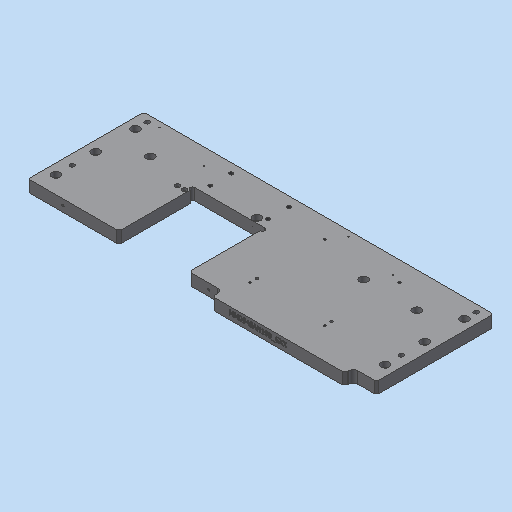
# Autodesk Inventor part: MM0948AN190_G01_101
Saved by Autodesk Inventor 2023.3 (Build 273359000, 359)
## iProperties
Created: 2023-03-23
Part Number: MM0948AN190_G01_101
Material: 1.2842 90MnCrV8
Document SubType Name: Modeling
Designer: Rose
Density: 7.85 g/cm^3
Appearance: silber AnP
Description: =<RBPARTNOTITLE2>
Mass: 32181.6 g
Surface Area: 4099.73 cm^2
Volume: 4099.57 cm^3
Project: 0850
RBMATERIAL: =<Material>
RBMATNO: =<Part Number>
RBPARTMADEOF: Präzisionsplatte 25 x 268 x 748 (FM)
RBPARTNO: SIEHE MNR
RBPARTNOTITLE1: manufactured part
RBPARTNOTITLE2: Anfertigungsteil
MaxAbmaße: 25 x 268,003 x 748 (FM)
AnP_Material_aktuell: =<Material>
AnP_Kommentar_aktuell: =<Comments>
AnP_TemplVers: 0
RBDRAWINGMISSINGSPEC: --
RBSURFACE2: chem. vernickelt
RBSURFACE: chemically nickel-coated
AnP_Kategorie: 1
AnP_Material: =<Material>
Name: MM0937AN110_G25_100.ipt
Author: FH/Wi
Keywords: =<RBPARTMADEOF>
Comments: =<RBSURFACE2>
Revision Number: 01
Autodesk Inventor part; units mm, degrees
ref_plane "YZ Plane" through (0, 0, 0) normal (1, 0, 0) x (0, 1, 0)
ref_plane "XZ Plane" through (0, 0, 0) normal (0, 1, 0) x (-1, 0, 0)
ref_plane "XY Plane" through (0, 0, 0) normal (0, 0, 1) x (1, 0, 0)
sketch "Skizze1" plane through (0, 0, 0) normal (0, 0, 1) x (1, 0, 0)
  line L0 (0, 178.6) -> (0, -196.6) projected
  line L1 (-523.6, 0) -> (523.6, 0) projected
  line L2 (-374, 125) -> (374, 125)
  line L3 (374, 125) -> (374, -143)
  line L4 (374, -143) -> (-374, -143)
  line L5 (-374, -143) -> (-374, 125)
  dimension "d1" = 748
  dimension "d259" = 125
  dimension "d260" = 143
  constraints: 8 end point, 2 parallel, 1 horizontal, 1 perpendicular, 1 other
  measures "d1" distance between parallel lines of L3 L5
  measures "d259" distance between parallel lines of L1 L2
  measures "d260" distance between parallel lines of L4 L1
extrude "Extrusion1" add sketch "Skizze1" along normal blind 25
sketch "Skizze2" plane through (0, 0, 25) normal (0, 0, 1) x (1, 0, 0)
  line L0 (0, 178.6) -> (0, -196.6) projected
  line L1 (-523.6, 0) -> (523.6, 0) projected
  line L2 (-352, 85) -> (-352, -85)
  line L3 (352, 85) -> (352, -85)
  line L4 (-374, 125) -> (-374, -143) projected
  point P0 (-352, 0)
  point P1 (352, 0)
  dimension "d4" = 22
  dimension "d5" = 170
  constraints: 4 coincident, 4 end point, 2 midpoint, 2 parallel, 1 perpendicular, 1 point on line, 1 symmetric about line
  measures "d4" distance from line of point (-352, 85) L4
  measures "d5" distance of L2.start L2.end
hole "Bohrung1" at (-352, 85, 25) at (-352, 0, 25) at (-352, -85, 25) at (352, 85, 25) at (352, 0, 25) at (352, -85, 25) direction (0, 0, -1) diameter 11 end through all counterbore diameter 18 counterbore depth 11 clearance for "Inbusschraube ISO 4762  versenkt" size "M10" standard "ISO"
sketch "Skizze3" plane through (0, 0, 25) normal (0, 0, 1) x (1, 0, 0)
  line L0 (0, 178.6) -> (0, -196.6) projected
  line L1 (-523.6, 0) -> (523.6, 0) projected
  circle A0 centre (-352, 85) radius 5.5 projected
  line L2 (-352, 85) -> (-352, 110)
  point P0 (-352, -50)
  point P1 (352, -50)
  point P2 (352, 110)
  dimension "d13" = 160
  dimension "d108" = 110
  constraints: 2 end point, 2 symmetric about line, 1 coincident, 1 perpendicular, 1 point on line
  measures "d13" distance of point (-352, -50) point (-352, 110)
  measures "d108" distance from line of L1 point (-352, 110)
hole "Bohrung2" at (-352, 110, 25) at (-352, -50, 25) at (352, -50, 25) at (352, 110, 25) direction (0, 0, -1) diameter 10 end through all
sketch "Skizze25" plane through (0, 0, 25) normal (0, 0, 1) x (1, 0, 0)
  line L0 (-324, -125) -> (-374, -125)
  line L1 (-374, -125) -> (-374, -143)
  line L2 (-374, -143) -> (-324, -143)
  line L3 (-324, -143) -> (-324, -125)
  line L4 (374, -125) -> (324, -125)
  line L5 (324, -125) -> (324, -143)
  line L6 (324, -143) -> (374, -143)
  line L7 (374, -143) -> (374, -125)
  point P0 (0, 0)
  dimension "d274" = 125
  dimension "d275" = 50
  constraints: 16 end point, 4 parallel, 2 coincident, 2 collinear, 2 horizontal, 2 perpendicular, 1 point on line
  measures "d274" distance from line of L0 point (0, 0)
  measures "d275" distance of L0.start L0.end
extrude "Extrusion3" cut sketch "Skizze25" against normal through all
fillet "Rundung1" radius 10 2 edges at (-324, -125, 12.5) (324, -125, 12.5)
chamfer "Fase1" distance 5 angle 45 6 edges at (-374, 125, 12.5) (374, 125, 12.5) (-374, -125, 12.5) (-324, -143, 12.5) (324, -143, 12.5) (374, -125, 12.5)
sketch "Skizze11" plane through (-379, -143, 0) normal (0, -1, 0) x (1, 0, 0)
  line L0 (455, 19) -> (579, 19) construction
  line L1 (579, 19) -> (579, 6) construction
  line L2 (579, 6) -> (455, 6) construction
  line L3 (455, 6) -> (455, 19) construction
  line L4 (698, 0) -> (60, 0) projected
  line L5 (5, 25) -> (5, 0) projected
  line L6 (464.5867, 8.7731) -> (463.2577, 8.7731)
  line L7 (463.2577, 8.7731) -> (463.2577, 17.3874)
  line L8 (463.2577, 17.3874) -> (460.6483, 11.5284)
  line L9 (460.6483, 11.5284) -> (459.8379, 11.5284)
  line L10 (459.8379, 11.5284) -> (457.2528, 17.3874)
  line L11 (457.2528, 17.3874) -> (457.2528, 8.7731)
  line L12 (457.2528, 8.7731) -> (456.013, 8.7731)
  line L13 (456.013, 8.7731) -> (456.013, 18.7731)
  line L14 (456.013, 18.7731) -> (457.8282, 18.7731)
  line L15 (457.8282, 18.7731) -> (460.3241, 13.2058)
  line L16 (460.3241, 13.2058) -> (462.7391, 18.7731)
  line L17 (462.7391, 18.7731) -> (464.5867, 18.7731)
  line L18 (464.5867, 18.7731) -> (464.5867, 8.7731)
  line L19 (475.1864, 8.7731) -> (473.8574, 8.7731)
  line L20 (473.8574, 8.7731) -> (473.8574, 17.3874)
  line L21 (473.8574, 17.3874) -> (471.248, 11.5284)
  line L22 (471.248, 11.5284) -> (470.4376, 11.5284)
  line L23 (470.4376, 11.5284) -> (467.8525, 17.3874)
  line L24 (467.8525, 17.3874) -> (467.8525, 8.7731)
  line L25 (467.8525, 8.7731) -> (466.6126, 8.7731)
  line L26 (466.6126, 8.7731) -> (466.6126, 18.7731)
  line L27 (466.6126, 18.7731) -> (468.4279, 18.7731)
  line L28 (468.4279, 18.7731) -> (470.9238, 13.2058)
  line L29 (470.9238, 13.2058) -> (473.3387, 18.7731)
  line L30 (473.3387, 18.7731) -> (475.1864, 18.7731)
  line L31 (475.1864, 18.7731) -> (475.1864, 8.7731)
  spline S0 degree 2 poles (483.1524, 13.7731) (483.1524, 11.0827) (481.5883, 8.5624) (479.9595, 8.5624) knots 0 0 0 1 2 2 2
  spline S1 degree 2 poles (479.9595, 8.5624) (478.3063, 8.5624) (476.7585, 11.1313) (476.7585, 13.765) knots 0 0 0 1 2 2 2
  spline S2 degree 2 poles (476.7585, 13.765) (476.7585, 16.4716) (478.3225, 18.9757) (479.9595, 18.9757) knots 0 0 0 1 2 2 2
  spline S3 degree 2 poles (479.9595, 18.9757) (481.6045, 18.9757) (483.1524, 16.3825) (483.1524, 13.7731) knots 0 0 0 1 2 2 2
  spline S4 degree 2 poles (481.4344, 10.7261) (481.6288, 11.2204) (481.7909, 12.7439) (481.7909, 13.7731) knots 0 0 0 1 2 2 2
  spline S5 degree 2 poles (481.7909, 13.7731) (481.7909, 14.8023) (481.6288, 16.3177) (481.4263, 16.8282) knots 0 0 0 1 2 2 2
  spline S6 degree 2 poles (481.4263, 16.8282) (481.2237, 17.3387) (480.5186, 17.8655) (479.9595, 17.8655) knots 0 0 0 1 2 2 2
  spline S7 degree 2 poles (479.9595, 17.8655) (479.4003, 17.8655) (478.6791, 17.3387) (478.4684, 16.812) knots 0 0 0 1 2 2 2
  spline S8 degree 2 poles (478.4684, 16.812) (478.2658, 16.3015) (478.1199, 14.7455) (478.1199, 13.765) knots 0 0 0 1 2 2 2
  spline S9 degree 2 poles (478.1199, 13.765) (478.1199, 12.7115) (478.2496, 11.3015) (478.4603, 10.7504) knots 0 0 0 1 2 2 2
  spline S10 degree 2 poles (478.4603, 10.7504) (478.6548, 10.2318) (479.376, 9.6726) (479.9595, 9.6726) knots 0 0 0 1 2 2 2
  spline S11 degree 2 poles (479.9595, 9.6726) (480.5105, 9.6726) (481.2318, 10.1994) (481.4344, 10.7261) knots 0 0 0 1 2 2 2
  spline S12 degree 2 poles (484.1572, 15.5235) (484.1572, 16.2934) (484.6596, 17.5737) (485.0972, 18.0357) knots 0 0 0 1 2 2 2
  spline S13 degree 2 poles (485.0972, 18.0357) (485.5105, 18.4814) (486.718, 18.9757) (487.3339, 18.9757) knots 0 0 0 1 2 2 2
  spline S14 degree 2 poles (487.3339, 18.9757) (488.0227, 18.9757) (489.141, 18.5138) (489.5543, 18.0762) knots 0 0 0 1 2 2 2
  spline S15 degree 2 poles (489.5543, 18.0762) (490.0729, 17.5251) (490.6402, 15.7423) (490.6402, 14.3728) knots 0 0 0 1 2 2 2
  spline S16 degree 2 poles (490.6402, 14.3728) (490.6402, 13.1329) (490.081, 10.9125) (489.5381, 10.175) knots 0 0 0 1 2 2 2
  spline S17 degree 2 poles (489.5381, 10.175) (488.9627, 9.3971) (487.342, 8.5786) (486.1588, 8.5786) knots 0 0 0 1 2 2 2
  spline S18 degree 2 poles (486.1588, 8.5786) (485.8914, 8.5786) (485.2836, 8.6353) (485.0243, 8.7164) knots 0 0 0 1 2 2 2
  line L32 (485.0243, 8.7164) -> (485.0243, 10.0049)
  line L33 (485.0243, 10.0049) -> (485.0891, 10.0049)
  spline S19 degree 2 poles (485.0891, 10.0049) (485.2593, 9.9076) (485.9724, 9.7374) (486.3371, 9.7374) knots 0 0 0 1 2 2 2
  spline S20 degree 2 poles (486.3371, 9.7374) (487.6499, 9.7374) (489.1491, 11.4716) (489.2545, 13.0762) knots 0 0 0 1 2 2 2
  spline S21 degree 2 poles (489.2545, 13.0762) (488.7196, 12.7115) (487.7472, 12.3793) (487.1718, 12.3793) knots 0 0 0 1 2 2 2
  spline S22 degree 2 poles (487.1718, 12.3793) (486.6207, 12.3793) (485.705, 12.6224) (485.2431, 12.9708) knots 0 0 0 1 2 2 2
  spline S23 degree 2 poles (485.2431, 12.9708) (484.7083, 13.3841) (484.1572, 14.6402) (484.1572, 15.5235) knots 0 0 0 1 2 2 2
  spline S24 degree 2 poles (489.2869, 14.6726) (489.2869, 15.6856) (488.9141, 16.966) (488.5818, 17.3144) knots 0 0 0 1 2 2 2
  spline S25 degree 2 poles (488.5818, 17.3144) (488.2901, 17.6386) (487.6823, 17.8817) (487.3258, 17.8817) knots 0 0 0 1 2 2 2
  spline S26 degree 2 poles (487.3258, 17.8817) (486.4992, 17.8817) (485.5186, 16.6985) (485.5186, 15.5802) knots 0 0 0 1 2 2 2
  spline S27 degree 2 poles (485.5186, 15.5802) (485.5186, 14.9481) (485.8428, 14.1297) (486.1994, 13.8379) knots 0 0 0 1 2 2 2
  spline S28 degree 2 poles (486.1994, 13.8379) (486.4587, 13.6272) (487.0989, 13.4895) (487.4716, 13.4895) knots 0 0 0 1 2 2 2
  spline S29 degree 2 poles (487.4716, 13.4895) (487.9011, 13.4895) (488.8898, 13.7893) (489.2626, 14.0405) knots 0 0 0 1 2 2 2
  spline S30 degree 2 poles (489.2626, 14.0405) (489.2707, 14.1378) (489.2869, 14.47) (489.2869, 14.6726) knots 0 0 0 1 2 2 2
  line L34 (498.3712, 12.2091) -> (497.1799, 12.2091)
  line L35 (497.1799, 12.2091) -> (497.1799, 8.7731)
  line L36 (497.1799, 8.7731) -> (495.8914, 8.7731)
  line L37 (495.8914, 8.7731) -> (495.8914, 12.2091)
  line L38 (495.8914, 12.2091) -> (491.4749, 12.2091)
  line L39 (491.4749, 12.2091) -> (491.4749, 13.6191)
  line L40 (491.4749, 13.6191) -> (495.9481, 18.7731)
  line L41 (495.9481, 18.7731) -> (497.1799, 18.7731)
  line L42 (497.1799, 18.7731) -> (497.1799, 13.2869)
  line L43 (497.1799, 13.2869) -> (498.3712, 13.2869)
  line L44 (498.3712, 13.2869) -> (498.3712, 12.2091)
  line L45 (495.8914, 13.2869) -> (495.8914, 17.1929)
  line L46 (495.8914, 17.1929) -> (492.5284, 13.2869)
  line L47 (492.5284, 13.2869) -> (495.8914, 13.2869)
  spline S31 degree 2 poles (502.4635, 8.5462) (501.718, 8.5462) (500.4943, 8.9919) (500.0648, 9.4052) knots 0 0 0 1 2 2 2
  spline S32 degree 2 poles (500.0648, 9.4052) (499.6434, 9.8104) (499.2058, 10.9125) (499.2058, 11.5365) knots 0 0 0 1 2 2 2
  spline S33 degree 2 poles (499.2058, 11.5365) (499.2058, 12.3468) (500.0729, 13.7083) (500.8995, 14.1135) knots 0 0 0 1 2 2 2
  line L48 (500.8995, 14.1135) -> (500.8995, 14.154)
  spline S34 degree 2 poles (500.8995, 14.154) (500.1621, 14.5835) (499.4489, 15.6045) (499.4489, 16.3663) knots 0 0 0 1 2 2 2
  spline S35 degree 2 poles (499.4489, 16.3663) (499.4489, 17.4927) (501.1507, 19) (502.4635, 19) knots 0 0 0 1 2 2 2
  spline S36 degree 2 poles (502.4635, 19) (503.825, 19) (505.47, 17.5737) (505.47, 16.4554) knots 0 0 0 1 2 2 2
  spline S37 degree 2 poles (505.47, 16.4554) (505.47, 15.7828) (504.684, 14.47) (503.9465, 14.0972) knots 0 0 0 1 2 2 2
  line L49 (503.9465, 14.0972) -> (503.9465, 14.0567)
  spline S38 degree 2 poles (503.9465, 14.0567) (504.8217, 13.6515) (505.7212, 12.4846) (505.7212, 11.5608) knots 0 0 0 1 2 2 2
  spline S39 degree 2 poles (505.7212, 11.5608) (505.7212, 10.2804) (503.8574, 8.5462) (502.4635, 8.5462) knots 0 0 0 1 2 2 2
  spline S40 degree 2 poles (504.3436, 11.4311) (504.3436, 12.047) (503.8574, 12.7763) (503.1686, 13.1491) knots 0 0 0 1 2 2 2
  spline S41 degree 2 poles (503.1686, 13.1491) (502.9417, 13.2788) (502.1799, 13.5786) (501.7018, 13.7731) knots 0 0 0 1 2 2 2
  spline S42 degree 2 poles (501.7018, 13.7731) (501.1507, 13.4084) (500.5592, 12.3225) (500.5592, 11.6337) knots 0 0 0 1 2 2 2
  spline S43 degree 2 poles (500.5592, 11.6337) (500.5592, 10.7261) (501.6532, 9.5429) (502.4797, 9.5429) knots 0 0 0 1 2 2 2
  spline S44 degree 2 poles (502.4797, 9.5429) (503.3225, 9.5429) (504.3436, 10.5559) (504.3436, 11.4311) knots 0 0 0 1 2 2 2
  spline S45 degree 2 poles (504.1572, 16.4392) (504.1572, 17.1118) (503.2577, 18.0113) (502.4554, 18.0113) knots 0 0 0 1 2 2 2
  spline S46 degree 2 poles (502.4554, 18.0113) (501.7261, 18.0113) (500.7942, 17.2091) (500.7942, 16.5203) knots 0 0 0 1 2 2 2
  spline S47 degree 2 poles (500.7942, 16.5203) (500.7942, 16.0259) (501.2723, 15.3371) (501.7504, 15.0616) knots 0 0 0 1 2 2 2
  spline S48 degree 2 poles (501.7504, 15.0616) (501.953, 14.9481) (502.812, 14.5511) (503.1605, 14.4376) knots 0 0 0 1 2 2 2
  spline S49 degree 2 poles (503.1605, 14.4376) (503.7439, 14.8833) (504.1572, 15.8314) (504.1572, 16.4392) knots 0 0 0 1 2 2 2
  line L50 (506.1507, 8.7731) -> (509.5219, 18.7731)
  line L51 (509.5219, 18.7731) -> (511.1588, 18.7731)
  line L52 (511.1588, 18.7731) -> (514.53, 8.7731)
  line L53 (514.53, 8.7731) -> (513.128, 8.7731)
  line L54 (513.128, 8.7731) -> (512.2204, 11.5689)
  line L55 (512.2204, 11.5689) -> (508.4036, 11.5689)
  line L56 (508.4036, 11.5689) -> (507.4959, 8.7731)
  line L57 (507.4959, 8.7731) -> (506.1507, 8.7731)
  line L58 (511.8558, 12.7034) -> (510.3079, 17.4117)
  line L59 (510.3079, 17.4117) -> (508.7682, 12.7034)
  line L60 (508.7682, 12.7034) -> (511.8558, 12.7034)
  line L61 (522.6337, 8.7731) -> (521.1426, 8.7731)
  line L62 (521.1426, 8.7731) -> (516.718, 17.3955)
  line L63 (516.718, 17.3955) -> (516.718, 8.7731)
  line L64 (516.718, 8.7731) -> (515.4781, 8.7731)
  line L65 (515.4781, 8.7731) -> (515.4781, 18.7731)
  line L66 (515.4781, 18.7731) -> (517.3663, 18.7731)
  line L67 (517.3663, 18.7731) -> (521.3938, 10.8558)
  line L68 (521.3938, 10.8558) -> (521.3938, 18.7731)
  line L69 (521.3938, 18.7731) -> (522.6337, 18.7731)
  line L70 (522.6337, 18.7731) -> (522.6337, 8.7731)
  line L71 (530.0405, 8.7731) -> (525.1621, 8.7731)
  line L72 (525.1621, 8.7731) -> (525.1621, 9.7942)
  line L73 (525.1621, 9.7942) -> (526.9773, 9.7942)
  line L74 (526.9773, 9.7942) -> (526.9773, 16.4959)
  line L75 (526.9773, 16.4959) -> (525.1621, 16.4959)
  line L76 (525.1621, 16.4959) -> (525.1621, 17.4117)
  spline S50 degree 2 poles (525.1621, 17.4117) (526.1912, 17.4117) (527.1637, 17.9951) (527.2285, 18.8055) knots 0 0 0 1 2 2 2
  line L77 (527.2285, 18.8055) -> (528.2658, 18.8055)
  line L78 (528.2658, 18.8055) -> (528.2658, 9.7942)
  line L79 (528.2658, 9.7942) -> (530.0405, 9.7942)
  line L80 (530.0405, 9.7942) -> (530.0405, 8.7731)
  spline S51 degree 2 poles (531.6045, 15.5235) (531.6045, 16.2934) (532.107, 17.5737) (532.5446, 18.0357) knots 0 0 0 1 2 2 2
  spline S52 degree 2 poles (532.5446, 18.0357) (532.9579, 18.4814) (534.1653, 18.9757) (534.7812, 18.9757) knots 0 0 0 1 2 2 2
  spline S53 degree 2 poles (534.7812, 18.9757) (535.47, 18.9757) (536.5883, 18.5138) (537.0016, 18.0762) knots 0 0 0 1 2 2 2
  spline S54 degree 2 poles (537.0016, 18.0762) (537.5203, 17.5251) (538.0875, 15.7423) (538.0875, 14.3728) knots 0 0 0 1 2 2 2
  spline S55 degree 2 poles (538.0875, 14.3728) (538.0875, 13.1329) (537.5284, 10.9125) (536.9854, 10.175) knots 0 0 0 1 2 2 2
  spline S56 degree 2 poles (536.9854, 10.175) (536.41, 9.3971) (534.7893, 8.5786) (533.6062, 8.5786) knots 0 0 0 1 2 2 2
  spline S57 degree 2 poles (533.6062, 8.5786) (533.3387, 8.5786) (532.731, 8.6353) (532.4716, 8.7164) knots 0 0 0 1 2 2 2
  line L81 (532.4716, 8.7164) -> (532.4716, 10.0049)
  line L82 (532.4716, 10.0049) -> (532.5365, 10.0049)
  spline S58 degree 2 poles (532.5365, 10.0049) (532.7066, 9.9076) (533.4198, 9.7374) (533.7844, 9.7374) knots 0 0 0 1 2 2 2
  spline S59 degree 2 poles (533.7844, 9.7374) (535.0972, 9.7374) (536.5964, 11.4716) (536.7018, 13.0762) knots 0 0 0 1 2 2 2
  spline S60 degree 2 poles (536.7018, 13.0762) (536.1669, 12.7115) (535.1945, 12.3793) (534.6191, 12.3793) knots 0 0 0 1 2 2 2
  spline S61 degree 2 poles (534.6191, 12.3793) (534.0681, 12.3793) (533.1524, 12.6224) (532.6904, 12.9708) knots 0 0 0 1 2 2 2
  spline S62 degree 2 poles (532.6904, 12.9708) (532.1556, 13.3841) (531.6045, 14.6402) (531.6045, 15.5235) knots 0 0 0 1 2 2 2
  spline S63 degree 2 poles (536.7342, 14.6726) (536.7342, 15.6856) (536.3614, 16.966) (536.0292, 17.3144) knots 0 0 0 1 2 2 2
  spline S64 degree 2 poles (536.0292, 17.3144) (535.7374, 17.6386) (535.1297, 17.8817) (534.7731, 17.8817) knots 0 0 0 1 2 2 2
  spline S65 degree 2 poles (534.7731, 17.8817) (533.9465, 17.8817) (532.966, 16.6985) (532.966, 15.5802) knots 0 0 0 1 2 2 2
  spline S66 degree 2 poles (532.966, 15.5802) (532.966, 14.9481) (533.2901, 14.1297) (533.6467, 13.8379) knots 0 0 0 1 2 2 2
  spline S67 degree 2 poles (533.6467, 13.8379) (533.906, 13.6272) (534.5462, 13.4895) (534.919, 13.4895) knots 0 0 0 1 2 2 2
  spline S68 degree 2 poles (534.919, 13.4895) (535.3485, 13.4895) (536.3371, 13.7893) (536.7099, 14.0405) knots 0 0 0 1 2 2 2
  spline S69 degree 2 poles (536.7099, 14.0405) (536.718, 14.1378) (536.7342, 14.47) (536.7342, 14.6726) knots 0 0 0 1 2 2 2
  spline S70 degree 2 poles (545.6078, 13.7731) (545.6078, 11.0827) (544.0438, 8.5624) (542.4149, 8.5624) knots 0 0 0 1 2 2 2
  spline S71 degree 2 poles (542.4149, 8.5624) (540.7618, 8.5624) (539.2139, 11.1313) (539.2139, 13.765) knots 0 0 0 1 2 2 2
  spline S72 degree 2 poles (539.2139, 13.765) (539.2139, 16.4716) (540.778, 18.9757) (542.4149, 18.9757) knots 0 0 0 1 2 2 2
  spline S73 degree 2 poles (542.4149, 18.9757) (544.06, 18.9757) (545.6078, 16.3825) (545.6078, 13.7731) knots 0 0 0 1 2 2 2
  spline S74 degree 2 poles (543.8898, 10.7261) (544.0843, 11.2204) (544.2464, 12.7439) (544.2464, 13.7731) knots 0 0 0 1 2 2 2
  spline S75 degree 2 poles (544.2464, 13.7731) (544.2464, 14.8023) (544.0843, 16.3177) (543.8817, 16.8282) knots 0 0 0 1 2 2 2
  spline S76 degree 2 poles (543.8817, 16.8282) (543.6791, 17.3387) (542.9741, 17.8655) (542.4149, 17.8655) knots 0 0 0 1 2 2 2
  spline S77 degree 2 poles (542.4149, 17.8655) (541.8558, 17.8655) (541.1345, 17.3387) (540.9238, 16.812) knots 0 0 0 1 2 2 2
  spline S78 degree 2 poles (540.9238, 16.812) (540.7212, 16.3015) (540.5754, 14.7455) (540.5754, 13.765) knots 0 0 0 1 2 2 2
  spline S79 degree 2 poles (540.5754, 13.765) (540.5754, 12.7115) (540.705, 11.3015) (540.9157, 10.7504) knots 0 0 0 1 2 2 2
  spline S80 degree 2 poles (540.9157, 10.7504) (541.1102, 10.2318) (541.8314, 9.6726) (542.4149, 9.6726) knots 0 0 0 1 2 2 2
  spline S81 degree 2 poles (542.4149, 9.6726) (542.966, 9.6726) (543.6872, 10.1994) (543.8898, 10.7261) knots 0 0 0 1 2 2 2
  line L83 (553.7682, 6.7634) -> (546.0535, 6.7634)
  line L84 (546.0535, 6.7634) -> (546.0535, 7.6305)
  line L85 (546.0535, 7.6305) -> (553.7682, 7.6305)
  line L86 (553.7682, 7.6305) -> (553.7682, 6.7634)
  spline S82 degree 2 poles (558.8655, 8.5786) (557.8039, 8.5786) (556.0454, 9.2269) (555.4133, 9.8833) knots 0 0 0 1 2 2 2
  spline S83 degree 2 poles (555.4133, 9.8833) (554.7812, 10.5478) (554.1086, 12.5089) (554.1086, 13.7812) knots 0 0 0 1 2 2 2
  spline S84 degree 2 poles (554.1086, 13.7812) (554.1086, 14.9887) (554.7893, 16.9011) (555.4214, 17.5818) knots 0 0 0 1 2 2 2
  spline S85 degree 2 poles (555.4214, 17.5818) (556.0292, 18.2382) (557.812, 18.9514) (558.8736, 18.9514) knots 0 0 0 1 2 2 2
  spline S86 degree 2 poles (558.8736, 18.9514) (559.3841, 18.9514) (560.3079, 18.8055) (560.7293, 18.6759) knots 0 0 0 1 2 2 2
  spline S87 degree 2 poles (560.7293, 18.6759) (561.0697, 18.5786) (561.8963, 18.222) (562.1475, 18.0924) knots 0 0 0 1 2 2 2
  line L87 (562.1475, 18.0924) -> (562.1475, 16.4878)
  line L88 (562.1475, 16.4878) -> (562.034, 16.4878)
  spline S88 degree 2 poles (562.034, 16.4878) (561.7828, 16.7066) (561.2561, 17.1037) (560.7699, 17.3306) knots 0 0 0 1 2 2 2
  spline S89 degree 2 poles (560.7699, 17.3306) (560.3647, 17.5332) (559.3193, 17.8006) (558.7196, 17.8006) knots 0 0 0 1 2 2 2
  spline S90 degree 2 poles (558.7196, 17.8006) (557.2771, 17.8006) (555.4943, 15.6288) (555.4943, 13.8217) knots 0 0 0 1 2 2 2
  spline S91 degree 2 poles (555.4943, 13.8217) (555.4943, 12.8169) (555.9643, 11.3096) (556.41, 10.7909) knots 0 0 0 1 2 2 2
  spline S92 degree 2 poles (556.41, 10.7909) (556.8395, 10.2723) (558.0551, 9.7293) (558.8169, 9.7293) knots 0 0 0 1 2 2 2
  spline S93 degree 2 poles (558.8169, 9.7293) (559.376, 9.7293) (560.4943, 9.8914) (560.8752, 10.0535) knots 0 0 0 1 2 2 2
  line L89 (560.8752, 10.0535) -> (560.8752, 12.6386)
  line L90 (560.8752, 12.6386) -> (558.5575, 12.6386)
  line L91 (558.5575, 12.6386) -> (558.5575, 13.8055)
  line L92 (558.5575, 13.8055) -> (562.188, 13.8055)
  line L93 (562.188, 13.8055) -> (562.188, 9.4376)
  spline S94 degree 2 poles (562.188, 9.4376) (561.9368, 9.3241) (561.0778, 8.9757) (560.7131, 8.8703) knots 0 0 0 1 2 2 2
  spline S95 degree 2 poles (560.7131, 8.8703) (560.2188, 8.7245) (559.4246, 8.5786) (558.8655, 8.5786) knots 0 0 0 1 2 2 2
  line L94 (570.7699, 8.7731) -> (569.2464, 8.7731)
  line L95 (569.2464, 8.7731) -> (566.8152, 12.7601)
  line L96 (566.8152, 12.7601) -> (564.3355, 8.7731)
  line L97 (564.3355, 8.7731) -> (562.9011, 8.7731)
  line L98 (562.9011, 8.7731) -> (566.0859, 13.7812)
  line L99 (566.0859, 13.7812) -> (562.9984, 18.7731)
  line L100 (562.9984, 18.7731) -> (564.5219, 18.7731)
  line L101 (564.5219, 18.7731) -> (566.9044, 14.859)
  line L102 (566.9044, 14.859) -> (569.3355, 18.7731)
  line L103 (569.3355, 18.7731) -> (570.7699, 18.7731)
  line L104 (570.7699, 18.7731) -> (567.6418, 13.846)
  line L105 (567.6418, 13.846) -> (570.7699, 8.7731)
  line L106 (578.752, 8.7731) -> (577.2285, 8.7731)
  line L107 (577.2285, 8.7731) -> (574.7974, 12.7601)
  line L108 (574.7974, 12.7601) -> (572.3177, 8.7731)
  line L109 (572.3177, 8.7731) -> (570.8833, 8.7731)
  line L110 (570.8833, 8.7731) -> (574.0681, 13.7812)
  line L111 (574.0681, 13.7812) -> (570.9806, 18.7731)
  line L112 (570.9806, 18.7731) -> (572.5041, 18.7731)
  line L113 (572.5041, 18.7731) -> (574.8865, 14.859)
  line L114 (574.8865, 14.859) -> (577.3177, 18.7731)
  line L115 (577.3177, 18.7731) -> (578.752, 18.7731)
  line L116 (578.752, 18.7731) -> (575.624, 13.846)
  line L117 (575.624, 13.846) -> (578.752, 8.7731)
  point P0 (738, 0)
  point P1 (683, 0)
  dimension "d127" = 124
  dimension "d129" = 13
  dimension "d130" = 6
  dimension "d279" = 450
  constraints: 2 other
  measures "d127" distance of L1.end L2.end
  measures "d129" distance of L2.end L0.start
  measures "d130" distance between parallel lines of L4 L2
  measures "d279" distance between parallel lines of L3 L5
emboss "Prägen1" sketch "Skizze11" operation cut depth 0.5 direction (0, 1, 0)
sketch "Skizze13" plane through (0, 0, 25) normal (0, 0, 1) x (1, 0, 0)
  line L0 (369, 125) -> (374, 120) projected
  line L1 (369, 125) -> (-369, 125) projected
  line L2 (-374, 120) -> (-369, 125) projected
  line L3 (-374, 120) -> (-374, -120) projected
  line L4 (-319, -143) -> (319, -143) projected
  line L5 (374, -120) -> (374, 120) projected
  circle A0 centre (352, -50) radius 5 projected
  circle A1 centre (-352, 110) radius 5 projected
  circle A2 centre (-352, -50) radius 5 projected
  circle A3 centre (352, 110) radius 5 projected
  circle A4 centre (352, 0) radius 9 projected
  circle A5 centre (-352, -85) radius 9 projected
  circle A6 centre (-352, 85) radius 9 projected
  circle A7 centre (-352, 0) radius 9 projected
  circle A8 centre (352, 85) radius 9 projected
  circle A9 centre (352, -85) radius 9 projected
  line L6 (-180, -143) -> (-30, -143)
  line L7 (-30, -143) -> (-30, 40)
  line L8 (-30, 40) -> (-180, 40)
  line L9 (-180, 40) -> (-180, -143)
  line L10 (-369, -125) -> (-334, -125) projected
  arc A10 (-324, -135) -> (-334, -125) centre (-334, -135) ccw projected
  line L11 (-324, -135) -> (-324, -138) projected
  line L12 (324, -138) -> (324, -135) projected
  arc A11 (334, -125) -> (324, -135) centre (334, -135) ccw projected
  line L13 (334, -125) -> (369, -125) projected
  line L14 (374, -120) -> (369, -125) projected
  line L15 (-369, -125) -> (-374, -120) projected
  line L16 (-319, -143) -> (-324, -138) projected
  line L17 (324, -138) -> (319, -143) projected
  point P0 (0, 0)
  dimension "d131" = 150
  dimension "d132" = 180
  dimension "d133" = 85
  constraints: 8 end point, 2 parallel, 1 horizontal, 1 perpendicular, 1 point on line
  measures "d131" distance of L7.end L8.end
  measures "d132" distance from line of L9 point (0, 0)
  measures "d133" distance between parallel lines of L1 L8
extrude "Extrusion2" cut sketch "Skizze13" against normal through all contours L4 L9 L8 L7
sketch "Skizze14" plane through (0, 0, 25) normal (0, 0, 1) x (1, 0, 0)
  line L0 (369, 125) -> (-369, 125) projected
  line L1 (-167, 105) -> (-43, 105)
  line L2 (-180, 40) -> (-30, 40) projected
  point P0 (0, 0)
  point P1 (-167, 60)
  point P2 (-43, 60)
  point P3 (-105, 40)
  point P4 (-105, 105)
  dimension "d136" = 20
  dimension "d137" = 45
  dimension "d232" = 124
  constraints: 3 vertical alignment, 2 end point, 2 horizontal alignment, 2 midpoint, 1 horizontal
  measures "d136" distance from line of L1.start L0
  measures "d137" distance of point (-167, 60) L1.start
  measures "d232" distance of L1.end L1.start
hole "Bohrung11" at (-167, 105, 25) at (-43, 105, 25) at (-167, 60, 25) at (-43, 60, 25) direction (0, 0, -1) diameter 8.376 end through all thread size "M10x1.5" designation "M10" class "6H" standard "ISO Metric profile"
sketch "Skizze15" plane through (0, 0, 25) normal (0, 0, 1) x (1, 0, 0)
  line L0 (-374, 120) -> (-374, -125) projected
  line L1 (-30, -143) -> (-180, -143) projected
  point P0 (0, 0)
  point P1 (-285, 50)
  point P2 (-57, 50)
  point P3 (171, 50)
  point P4 (-374, -138)
  point P5 (285, 50)
  point P6 (-369, -143)
  dimension "d147" = 89
  dimension "d148" = 228
  dimension "d152" = 114
  dimension "d255" = 570
  dimension "d261" = 50
  constraints: 3 horizontal alignment
  measures "d147" distance from line of point (-285, 50) L0
  measures "d148" distance of point (-57, 50) point (-285, 50)
  measures "d152" distance of point (285, 50) point (171, 50)
  measures "d255" distance of point (285, 50) point (-285, 50)
  measures "d261" vertical distance of point (0, 0) point (-285, 50)
hole "Bohrung12" at (-285, 50, 25) at (-57, 50, 25) at (171, 50, 25) at (285, 50, 25) direction (0, 0, -1) diameter 11 end through all counterbore diameter 18 counterbore depth 11 clearance for "Inbusschraube ISO 4762  versenkt" size "M10" standard "ISO"
sketch "Skizze16" plane through (0, 0, 25) normal (0, 0, 1) x (1, 0, 0)
  circle A0 centre (171, 50) radius 9 projected
  circle A1 centre (-285, 50) radius 9 projected
  circle A2 centre (-57, 50) radius 9 projected
  circle A3 centre (285, 50) radius 9 projected
  circle A4 centre (-167, 60) radius 4.188 projected
  circle A5 centre (-167, 105) radius 4.188 projected
  circle A6 centre (-43, 105) radius 4.188 projected
  circle A7 centre (-43, 60) radius 4.188 projected
  circle A8 centre (352, -85) radius 9 projected
  circle A9 centre (352, 85) radius 9 projected
  circle A10 centre (-352, 0) radius 9 projected
  circle A11 centre (-352, 85) radius 9 projected
  circle A12 centre (-352, -85) radius 9 projected
  circle A13 centre (352, 0) radius 9 projected
  circle A14 centre (352, 110) radius 5 projected
  circle A15 centre (-352, -50) radius 5 projected
  circle A16 centre (-352, 110) radius 5 projected
  circle A17 centre (352, -50) radius 5 projected
  line L0 (-180, -143) -> (-180, 40) projected
  line L1 (-180, 40) -> (-30, 40) projected
  line L2 (-30, 40) -> (-30, -143) projected
  line L3 (-319, -143) -> (-180, -143) projected
  line L4 (374, -120) -> (374, 120) projected
  line L5 (369, 125) -> (374, 120) projected
  line L6 (369, 125) -> (-369, 125) projected
  line L7 (-374, 120) -> (-369, 125) projected
  line L8 (-374, 120) -> (-374, -120) projected
  line L9 (-30, -143) -> (319, -143) projected
  line L10 (324, -138) -> (324, -135) projected
  arc A18 (334, -125) -> (324, -135) centre (334, -135) ccw projected
  line L11 (334, -125) -> (369, -125) projected
  line L12 (-369, -125) -> (-334, -125) projected
  arc A19 (-324, -135) -> (-334, -125) centre (-334, -135) ccw projected
  line L13 (-324, -135) -> (-324, -138) projected
  line L14 (324, -138) -> (319, -143) projected
  line L15 (374, -120) -> (369, -125) projected
  line L16 (-369, -125) -> (-374, -120) projected
  line L17 (-319, -143) -> (-324, -138) projected
  point P0 (0, 0)
  point P1 (-180, 35)
  point P2 (-30, 35)
  dimension "d162" = 5
  dimension "d163" = 5
  constraints: 2 point on line
  measures "d162" distance from line of L1 point (-180, 35)
  measures "d163" distance from line of L1 point (-30, 35)
hole "Bohrung13" at (-180, 35, 25) at (-30, 35, 25) direction (0, 0, -1) diameter 10 end through all
sketch "Skizze18" plane through (-369, 125, 0) normal (0, 1, 0) x (1, 0, 0)
  line L0 (369, 5) -> (369, -30) projected
  line L1 (892.6, 0) -> (-154.6, 0) projected
  line L2 (189, -25) -> (339, -25) projected
  line L3 (264, -25) -> (264, 0)
  point P0 (369, 0)
  point P1 (248.1, -12.5)
  point P2 (208.1, -12.5)
  dimension "d186" = 12.5
  dimension "d188" = 40
  dimension "d233" = 15.9
  constraints: 2 end point, 1 horizontal alignment, 1 midpoint, 1 perpendicular, 1 point on line
  measures "d186" distance from line of L1 point (248.1, -12.5)
  measures "d188" distance of point (248.1, -12.5) point (208.1, -12.5)
  measures "d233" distance from line of L3 point (248.1, -12.5)
hole "Bohrung15" at (-120.9, 125, 12.5) at (-160.9, 125, 12.5) direction (0, -1, 0) diameter 4.917 depth 12 tip angle 118 thread size "M6x1" designation "M6" class "6H" standard "ISO Metric profile"
sketch "Skizze19" plane through (-369, 125, 0) normal (0, 1, 0) x (1, 0, 0)
  line L0 (369, 5) -> (369, -30) projected
  line L1 (892.6, 0) -> (-154.6, 0) projected
  circle A0 centre (248.1, -12.5) radius 2.4585 projected
  circle A1 centre (208.1, -12.5) radius 2.4585 projected
  point P0 (369, 0)
  point P1 (48.1, -12.5)
  point P2 (148.1, -12.5)
  point P3 (308.1, -12.5)
  point P4 (508.1, -12.5)
  dimension "d196" = 12.5
  dimension "d198" = 100
  dimension "d200" = 200
  dimension "d256" = 160
  dimension "d257" = 40
  dimension "d258" = 60
  constraints: 3 horizontal alignment
  measures "d196" distance from line of L1 point (148.1, -12.5)
  measures "d198" distance of point (48.1, -12.5) point (148.1, -12.5)
  measures "d200" distance of point (508.1, -12.5) point (308.1, -12.5)
  measures "d256" distance of point (308.1, -12.5) point (148.1, -12.5)
  measures "d257" distance of A0.centre A1.centre
  measures "d258" distance of point (308.1, -12.5) A0.centre
hole "Bohrung16" at (-320.9, 125, 12.5) at (-220.9, 125, 12.5) at (-60.9, 125, 12.5) at (139.1, 125, 12.5) direction (0, -1, 0) diameter 3.242 depth 11.8 tip angle 118 thread size "M4x0.7" designation "M4" class "6H" standard "ISO Metric profile"
chamfer "Fase3" distance 10 angle 45 2 edges at (-180, -143, 12.5) (-30, -143, 12.5)
sketch "Skizze22" plane through (-123.43, 16.1933, 25) normal (0, 0, 1) x (1, 0, 0)
  line L0 (103.43, -159.1933) -> (447.43, -159.1933) projected
  point P0 (178.43, -93.1933)
  point P1 (178.43, 66.8067)
  point P2 (338.43, 66.8067)
  point P3 (338.43, -93.1933)
  point P4 (492.43, -159.1933)
  point P5 (123.43, -16.1933)
  dimension "d236" = 160
  dimension "d235" = 160
  dimension "d254" = 55
  dimension "d263" = 77
  constraints: 2 horizontal alignment, 2 vertical alignment
  measures "d236" distance of point (338.43, -93.193) point (178.43, -93.193)
  measures "d235" distance of point (338.43, -93.193) point (338.43, 66.807)
  measures "d254" horizontal distance of point (178.43, -93.193) point (123.43, -16.193)
  measures "d263" vertical distance of point (338.43, -93.193) point (123.43, -16.193)
hole "Bohrung19" at (55, -77, 25) at (55, 83, 25) at (215, 83, 25) at (215, -77, 25) direction (0, 0, -1) diameter 4.917 end through all thread size "M6x1" designation "M6" class "6H" standard "ISO Metric profile"
sketch "Skizze23" plane through (0, -9, 25) normal (0, 0, 1) x (1, 0, 0)
  circle A0 centre (55, -68) radius 2.4585 projected
  circle A1 centre (215, -68) radius 2.4585 projected
  point P0 (0, 0)
  point P1 (55, -53)
  point P2 (215, -53)
  dimension "d299" = 15
  constraints: 2 vertical alignment, 1 horizontal alignment
  measures "d299" distance of A1.centre point (215, -53)
hole "Bohrung20" at (55, -62, 25) at (215, -62, 25) direction (0, 0, -1) diameter 6 depth 12 tip angle 118
sketch "Skizze21" plane through (0, 0, 25) normal (0, 0, 1) x (1, 0, 0)
  line L0 (0, 178.6) -> (0, -196.6) projected
  line L1 (-523.6, 0) -> (523.6, 0) projected
  line L2 (-329, 113) -> (-210, 113) construction
  line L3 (-210, 113) -> (-210, 90) construction
  line L4 (-210, 90) -> (-329, 90) construction
  line L5 (-329, 90) -> (-329, 113) construction
  line L6 (75.5, 113) -> (194.5, 113) construction
  line L7 (194.5, 113) -> (194.5, 90) construction
  line L8 (194.5, 90) -> (75.5, 90) construction
  line L9 (75.5, 90) -> (75.5, 113) construction
  circle A0 centre (55, 83) radius 2.4585 projected
  circle A1 centre (215, 83) radius 2.4585 projected
  line L10 (55, 83) -> (215, 83)
  point P0 (0, 0)
  point P1 (135, 90)
  point P2 (135, 83)
  dimension "d219" = 119
  dimension "d220" = 23
  dimension "d221" = 90
  dimension "d222" = 210
  dimension "d223" = 90
  constraints: 18 end point, 4 coincident, 4 parallel, 3 horizontal, 2 equal length, 2 midpoint, 2 perpendicular, 1 vertical alignment
  measures "d219" distance of L3.end L4.end
  measures "d220" distance of L2.end L3.end
  measures "d221" distance between parallel lines of L1 L4
  measures "d222" distance between parallel lines of L0 L3
  measures "d223" distance between parallel lines of L1 L8
hole "Bohrung18" at (-329, 113, 25) at (-210, 90, 25) at (75.5, 113, 25) at (194.5, 90, 25) direction (0, 0, -1) diameter 2.459 depth 9 tip angle 118 thread size "M3x0.5" designation "M3" class "6H" standard "ISO Metric profile"
sketch "Skizze27" plane through (0, 0, 25) normal (0, 0, 1) x (1, 0, 0)
  line L0 (-374, 120) -> (-374, -120) projected
  line L1 (-319, -143) -> (-190, -143) projected
  line L2 (-20, -143) -> (319, -143) projected
  line L3 (-374, -122) -> (41, -122)
  line L4 (41, -122) -> (41, -143)
  line L5 (41, -143) -> (-374, -143)
  line L6 (-374, -143) -> (-374, -122)
  point P0 (0, 0)
  dimension "d290" = 415
  dimension "d292" = 122
  constraints: 8 end point, 2 parallel, 2 point on line, 1 horizontal, 1 perpendicular
  measures "d290" distance of L3.start L3.end
  measures "d292" distance from line of point (0, 0) L3
extrude "Extrusion4" cut sketch "Skizze27" against normal through all
sketch "Skizze24" plane through (-379, -122, 0) normal (0, -1, 0) x (1, 0, 0)
  line L0 (698, 0) -> (420, 0) projected
  point P0 (379, 0)
  point P1 (79, 12.5)
  point P2 (391, 12.5)
  point P3 (189, 0)
  point P4 (359, 0)
  dimension "d271" = 12.5
  dimension "d272" = 312
  dimension "d273" = 300
  constraints: 1 horizontal alignment
  measures "d271" distance from line of L0 point (79, 12.5)
  measures "d272" distance of point (391, 12.5) point (79, 12.5)
  measures "d273" horizontal distance of point (79, 12.5) point (379, 0)
hole "Bohrung21" at (-300, -122, 12.5) at (12, -122, 12.5) direction (0, 1, 0) diameter 4.917 depth 17.1 tip angle 118 thread size "M6x1" designation "M6" class "6H" standard "ISO Metric profile"
sketch "Skizze26" plane through (0, 0, 0) normal (0, 0, -1) x (-1, 0, 0)
  line L0 (-319, -143) -> (20, -143) projected
  circle A0 centre (-55, -77) radius 2.4585 projected
  point P0 (0, 0)
  point P1 (-32, -133)
  dimension "d287" = 32
  dimension "d288" = 10
  dimension "d289" = 23
  measures "d287" horizontal distance of point (-32, -133) point (0, 0)
  measures "d288" distance from line of point (-32, -133) L0
  measures "d289" horizontal distance of A0.centre point (-32, -133)
hole "Bohrung22" [suppressed]
fillet "Rundung2" radius 10 1 edges at (41, -122, 12.5)
chamfer "Fase4" distance 5 angle 45 3 edges at (-180, -122, 12.5) (-30, -122, 12.5) (41, -143, 12.5)
sketch "Skizze28" plane through (0, 0, 25) normal (0, 0, 1) x (1, 0, 0)
  line L0 (-180, -117) -> (-180, 30) projected
  line L1 (-180, 40) -> (-30, 40) projected
  point P0 (0, 0)
  point P1 (-187, 25)
  point P2 (-202, 25)
  dimension "d300" = 15
  dimension "d301" = 7
  dimension "d309" = 15
  constraints: 1 horizontal alignment
  measures "d300" distance of point (-187, 25) point (-202, 25)
  measures "d301" distance from line of L0 point (-187, 25)
  measures "d309" distance from line of point (-187, 25) L1
hole "Bohrung23" at (-187, 25, 25) at (-202, 25, 25) direction (0, 0, -1) diameter 5.5 end through all counterbore diameter 10 counterbore depth 5.7 clearance for "Inbusschraube ISO 4762  versenkt" size "M5" standard "ISO"
equation "\"d258\" = -0.5 * d257 + 0.5 * d256"
equation "\"d223\" = d221"
